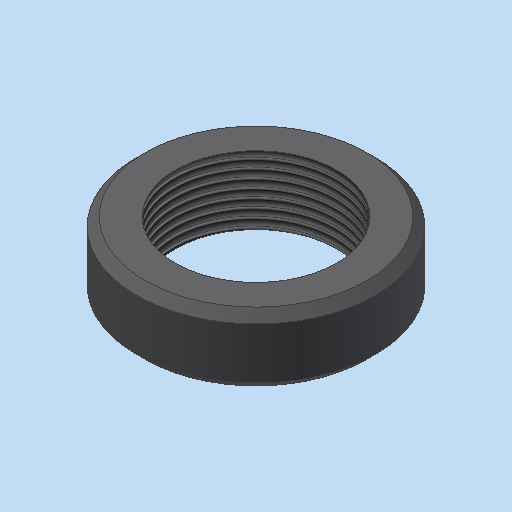
# Autodesk Inventor part: MN0555AN200_G01_201
Saved by Autodesk Inventor 2023.3 (Build 273359000, 359)
## iProperties
Created: 2013-03-20
Part Number: MN0555AN200_G01_201
Material: 1.2099 X5CrS12
Document SubType Name: Modeling
Designer: brt9bw
Density: 7.85 g/cm^3
Mass: 20.3448 g
Surface Area: 17.4288 cm^2
Volume: 2.59169 cm^3
Appearance: Stahl - rostfrei AnP
Description: =<RBPARTNOTITLE2>
RBPARTNOTITLE1: manufactured part
RBPARTMADEOF: Ø28 x 8 (FM)
RBPARTNOTITLE2: Anfertigungsteil
RBPARTNO: SIEHE MNR
RBMATNO: =<Part Number>
RBMATERIAL: =<Material>
RBGBDIM_01: 0,000 mm
RBGBDIM_04: 0,000 mm
RBGBDIM_03: 0,000 mm
RBGBDIM_02: 0,000 mm
AnP_Kommentar_aktuell: =<Comments>
AnP_Material_aktuell: =<Material>
MaxAbmaße: 8 x 28 x 28 (FM)
RBDRAWINGMISSINGSPEC: --
AnP_Kategorie: 1
RBGBREMARKSINDEX: E
RBSURFACE: --
AnP_Material: =<Material>
RBSURFACE2: --
Author: brt9bw
Keywords: =<RBPARTMADEOF>
Comments: =<RBSURFACE2>
Revision Number: 01
Autodesk Inventor part; units mm, degrees
ref_plane "YZ Plane" through (0, 0, 0) normal (1, 0, 0) x (0, 1, 0)
ref_plane "XZ Plane" through (0, 0, 0) normal (0, 1, 0) x (-1, 0, 0)
ref_plane "XY Plane" through (0, 0, 0) normal (0, 0, 1) x (1, 0, 0)
sketch "Skizze1" plane through (0, 0, 0) normal (0, 0, 1) x (1, 0, 0)
  circle A0 centre (0, 0) radius 14
  dimension "d0" = 28
  constraints: 1 centre point, 1 coincident
  measures "d0" diameter of A0
extrude "Extrusion1" add sketch "Skizze1" along normal blind 8
chamfer "Fase1" distance 1 angle 45 2 edges at (-14, 0, 8) (-14, 0, 0)
sketch "Skizze2" plane through (0, 0, 8) normal (0, 0, 1) x (1, 0, 0)
  circle A0 centre (0, 0) radius 13 projected
  constraints: 1 coincident
hole "Bohrung1" at (0, 0, 8) direction (0, 0, -1) diameter 18.917 end through all thread size "M20x1" class "6H" standard "ISO Metric profile"
equation "\"RBGBDIM_01\" = 0"
equation "\"RBGBDIM_02\" = 0"
equation "\"RBGBDIM_03\" = 0"
equation "\"RBGBDIM_04\" = 0"
